Autodesk Fusion 360 part; units mm, degrees
(part 2 of 2)
equation "d182 = ( xiao_cx - ( plug_w / 2 + 0.5 mm + ( 8.9 mm + xiao_gap + 1.2 mm - plug_w / 2 - 0.5 mm ) / 2 ) ) + ( ( 8.9 mm + xiao_gap + 1.2 mm - plug_w / 2 - 0.5 mm ) ) / 2"
equation "d183 = ( comp_zc + xiao_z0 - xiao_gap - 0.6 mm ) + ( 1.2 mm ) / 2"
equation "d184 = ( xiao_cx + ( plug_w / 2 + 0.5 mm + ( 8.9 mm + xiao_gap + 1.2 mm - plug_w / 2 - 0.5 mm ) / 2 ) ) - ( ( 8.9 mm + xiao_gap + 1.2 mm - plug_w / 2 - 0.5 mm ) ) / 2"
equation "d185 = ( xiao_cx + ( plug_w / 2 + 0.5 mm + ( 8.9 mm + xiao_gap + 1.2 mm - plug_w / 2 - 0.5 mm ) / 2 ) ) + ( ( 8.9 mm + xiao_gap + 1.2 mm - plug_w / 2 - 0.5 mm ) ) / 2"
equation "d186 = ( comp_zc + xiao_z0 - xiao_gap - 0.6 mm ) + ( 1.2 mm ) / 2"
equation "d187 = -( xiao_standoff + 2.2 mm )"
equation "d191 = ( xiao_cx ) - ( usb_ch_w ) / 2"
equation "d192 = ( xiao_cx ) + ( usb_ch_w ) / 2"
equation "d193 = -( ( -face_y + comp_depth - xiao_standoff + 1.6 mm ) - ( usb_ch_d ) / 2 )"
equation "d194 = -( ( -face_y + comp_depth - xiao_standoff + 1.6 mm ) + ( usb_ch_d ) / 2 )"
equation "d195 = comp_zc + xiao_z0 + 9.3 mm"
equation "d197 = -face_y + comp_depth - xiao_standoff + 1.6 mm"
equation "d199 = 80 mm - ( -face_y + comp_depth - xiao_standoff + 1.6 mm )"
equation "d201 = -face_y - 30 mm"
equation "d203 = plate_d"
equation "d204 = comp_zc + face_dz"
equation "d205 = 30 mm + plate_t"
equation "d208 = body_chamfer_bot"
equation "d210 = body_fillet_top"
equation "d211 = -face_y + plate_t"
equation "d213 = -( ( 0 mm ) - ( mouth_w + mouth_hole_d + 4.8 mm ) / 2 )"
equation "d214 = ( 0 mm ) + ( mouth_w + mouth_hole_d + 4.8 mm ) / 2"
equation "d215 = ( comp_zc + mouth_dz - mouth_drop / 2 ) - ( mouth_drop + mouth_hole_d + 1.2 mm ) / 2"
equation "d216 = ( comp_zc + mouth_dz - mouth_drop / 2 ) + ( mouth_drop + mouth_hole_d + 1.2 mm ) / 2"
equation "d217 = -( plate_t - mouth_front )"
equation "d219 = -face_y + mouth_front + 0.5 mm"
equation "d221 = mouth_hole_d"
equation "d222 = -( -10.5000 mm )"
equation "d224 = mouth_hole_d"
equation "d225 = -( -7.7784 mm )"
equation "d227 = mouth_hole_d"
equation "d228 = -( -4.1344 mm )"
equation "d230 = mouth_hole_d"
equation "d232 = mouth_hole_d"
equation "d235 = mouth_hole_d"
equation "d238 = mouth_hole_d"
equation "d240 = -( 20 mm )"
equation "d242 = mag_d"
equation "d244 = comp_zc + face_dz + 0.0 mm"
equation "d245 = mag_d"
equation "d246 = -( -34.0 mm )"
equation "d247 = mag_d"
equation "d249 = comp_zc + face_dz + -24.0 mm"
equation "d250 = mag_d"
equation "d251 = -( -24.0 mm )"
equation "d252 = comp_zc + face_dz + -24.0 mm"
equation "d253 = -( mag_t )"
equation "d255 = -face_y + plate_t + 0.2 mm"
equation "d257 = -( ( 0 mm ) - ( vb_size ) / 2 )"
equation "d258 = ( 0 mm ) + ( vb_size ) / 2"
equation "d259 = ( comp_zc + vb_z0 + vb_h / 2 ) - ( vb_h ) / 2"
equation "d260 = ( comp_zc + vb_z0 + vb_h / 2 ) + ( vb_h ) / 2"
equation "d261 = vb_size"
equation "d263 = comp_zc + vb_z0 + vb_h"
equation "d265 = -( ( vb_size / 2 - 9.43 mm ) - ( 12.7 mm ) / 2 )"
equation "d266 = ( vb_size / 2 - 9.43 mm ) + ( 12.7 mm ) / 2"
equation "d267 = -( ( -face_y + plate_t + 0.2 mm + 4.35 mm ) - ( 2.54 mm ) / 2 )"
equation "d268 = -( ( -face_y + plate_t + 0.2 mm + 4.35 mm ) + ( 2.54 mm ) / 2 )"
equation "d271 = -( ( vb_size / 2 - 8.16 mm ) - ( 10.16 mm ) / 2 )"
equation "d272 = ( vb_size / 2 - 8.16 mm ) + ( 10.16 mm ) / 2"
equation "d273 = -( ( -face_y + plate_t + 0.2 mm + vb_size - 4.35 mm ) - ( 2.54 mm ) / 2 )"
equation "d274 = -( ( -face_y + plate_t + 0.2 mm + vb_size - 4.35 mm ) + ( 2.54 mm ) / 2 )"
equation "d277 = -face_y + comp_depth - xiao_standoff"
equation "d279 = ( xiao_cx ) - ( 17.8 mm ) / 2"
equation "d280 = ( xiao_cx ) + ( 17.8 mm ) / 2"
equation "d281 = ( comp_zc + xiao_z0 + 10.5 mm ) - ( 21.0 mm ) / 2"
equation "d282 = ( comp_zc + xiao_z0 + 10.5 mm ) + ( 21.0 mm ) / 2"
equation "d283 = -( 1.2 mm )"
equation "d285 = ( xiao_cx ) - ( 13 mm ) / 2"
equation "d286 = ( xiao_cx ) + ( 13 mm ) / 2"
equation "d287 = ( comp_zc + xiao_z0 + 14 mm ) - ( 12 mm ) / 2"
equation "d288 = ( comp_zc + xiao_z0 + 14 mm ) + ( 12 mm ) / 2"
equation "d291 = ( xiao_cx ) - ( 9.0 mm ) / 2"
equation "d292 = ( xiao_cx ) + ( 9.0 mm ) / 2"
equation "d293 = ( comp_zc + xiao_z0 + 2.65 mm ) - ( 7.3 mm ) / 2"
equation "d294 = ( comp_zc + xiao_z0 + 2.65 mm ) + ( 7.3 mm ) / 2"
equation "d297 = -face_y + comp_depth - xiao_standoff - 1.2 mm"
equation "d299 = ( xiao_cx - 7.62 mm ) - ( 2.54 mm ) / 2"
equation "d300 = ( xiao_cx - 7.62 mm ) + ( 2.54 mm ) / 2"
equation "d301 = ( comp_zc + xiao_z0 + 10.5 mm ) - ( 17.78 mm ) / 2"
equation "d302 = ( comp_zc + xiao_z0 + 10.5 mm ) + ( 17.78 mm ) / 2"
equation "d303 = -( 16.5 mm )"
equation "d305 = ( xiao_cx + 7.62 mm ) - ( 2.54 mm ) / 2"
equation "d306 = ( xiao_cx + 7.62 mm ) + ( 2.54 mm ) / 2"
equation "d307 = ( comp_zc + xiao_z0 + 10.5 mm ) - ( 17.78 mm ) / 2"
equation "d308 = ( comp_zc + xiao_z0 + 10.5 mm ) + ( 17.78 mm ) / 2"
equation "d309 = -( 16.5 mm )"
equation "d311 = comp_zc + xiao_z0 - 1.0 mm"
equation "d313 = ( xiao_cx ) - ( plug_w ) / 2"
equation "d314 = ( xiao_cx ) + ( plug_w ) / 2"
equation "d315 = -( ( -face_y + comp_depth - xiao_standoff + 1.6 mm ) - ( plug_t ) / 2 )"
equation "d316 = -( ( -face_y + comp_depth - xiao_standoff + 1.6 mm ) + ( plug_t ) / 2 )"
equation "d317 = -( plug_len )"
equation "d319 = comp_zc + xiao_z0 - 1.0 mm - plug_len"
equation "d321 = cable_d"
equation "d322 = xiao_cx"
equation "d323 = -( -face_y + comp_depth - xiao_standoff + 1.6 mm )"
equation "d324 = -( ( comp_zc + xiao_z0 - 1.0 mm - plug_len ) - groove_h / 2 - 5 mm )"
equation "d326 = -face_y + comp_depth - xiao_standoff + 1.6 mm + 5 mm"
equation "d328 = cable_d"
equation "d329 = xiao_cx"
equation "d330 = groove_h / 2"
equation "d331 = 75 mm - ( -face_y + comp_depth - xiao_standoff + 1.6 mm )"
equation "d345 = eye_t"
equation "d348 = eye_round"
equation "d349 = arm_x0"
equation "d353 = peg_hole_d"
equation "d354 = arm_z + ( -6.0 mm )"
equation "d355 = peg_hole_d"
equation "d356 = arm_z + ( 10.0 mm )"
equation "d357 = -( peg_hole_depth )"
equation "d359 = -arm_x0"
equation "d361 = -( 20 mm )"
equation "d363 = peg_hole_d"
equation "d364 = arm_z + ( -6.0 mm )"
equation "d365 = peg_hole_d"
equation "d366 = arm_z + ( 10.0 mm )"
equation "d367 = peg_hole_depth"
equation "d373 = peg_hole_depth + 10 mm"
equation "d379 = peg_hole_depth + 10 mm"
equation "d385 = arm_x0"
equation "d387 = -( ( 0 mm ) - ( arm_r * 3 ) / 2 )"
equation "d388 = ( 0 mm ) + ( arm_r * 3 ) / 2"
equation "d389 = -( ( arm_z ) - ( ( arm_top + arm_bot ) * 3 ) / 2 )"
equation "d390 = ( arm_z ) + ( ( arm_top + arm_bot ) * 3 ) / 2"
equation "d391 = -( arm_out + 5 mm )"
equation "d393 = peg_hole_d"
equation "d394 = arm_z + ( -6.0 mm )"
equation "d395 = peg_hole_d"
equation "d396 = arm_z + ( 10.0 mm )"
equation "d397 = peg_hole_depth"
equation "d399 = ( 68.14721451327155 mm ) - ( 26.000000000000007 mm ) / 2"
equation "d400 = ( 68.14721451327155 mm ) + ( 26.000000000000007 mm ) / 2"
equation "d401 = -( ( 0 mm ) - ( foot_w ) / 2 )"
equation "d402 = ( 0 mm ) + ( foot_w ) / 2"
equation "d403 = foot_h"
equation "d406 = foot_w / 2 - 0.6 mm"
equation "d408 = foot_toe"
equation "d410 = body_chamfer_bot"
equation "d412 = body_fillet_top"
equation "d415 = peg_hole_d"
equation "d417 = peg_hole_depth + 3 mm"
named bodies: "本体", "顔のふた", "顔のふた_削り型", "参照_Voice Base", "参照_Voice Baseのコネクタ", "参照_Voice Baseのコネクタ (1)", "参照_XIAO", "参照_XIAOのシールド", "参照_XIAOのUSB", "参照_XIAOのコネクタ", "参照_XIAOのコネクタ (1)", "参照_USBプラグ", "参照_ケーブル", "参照_ケーブル (1)", "足_削り型"
